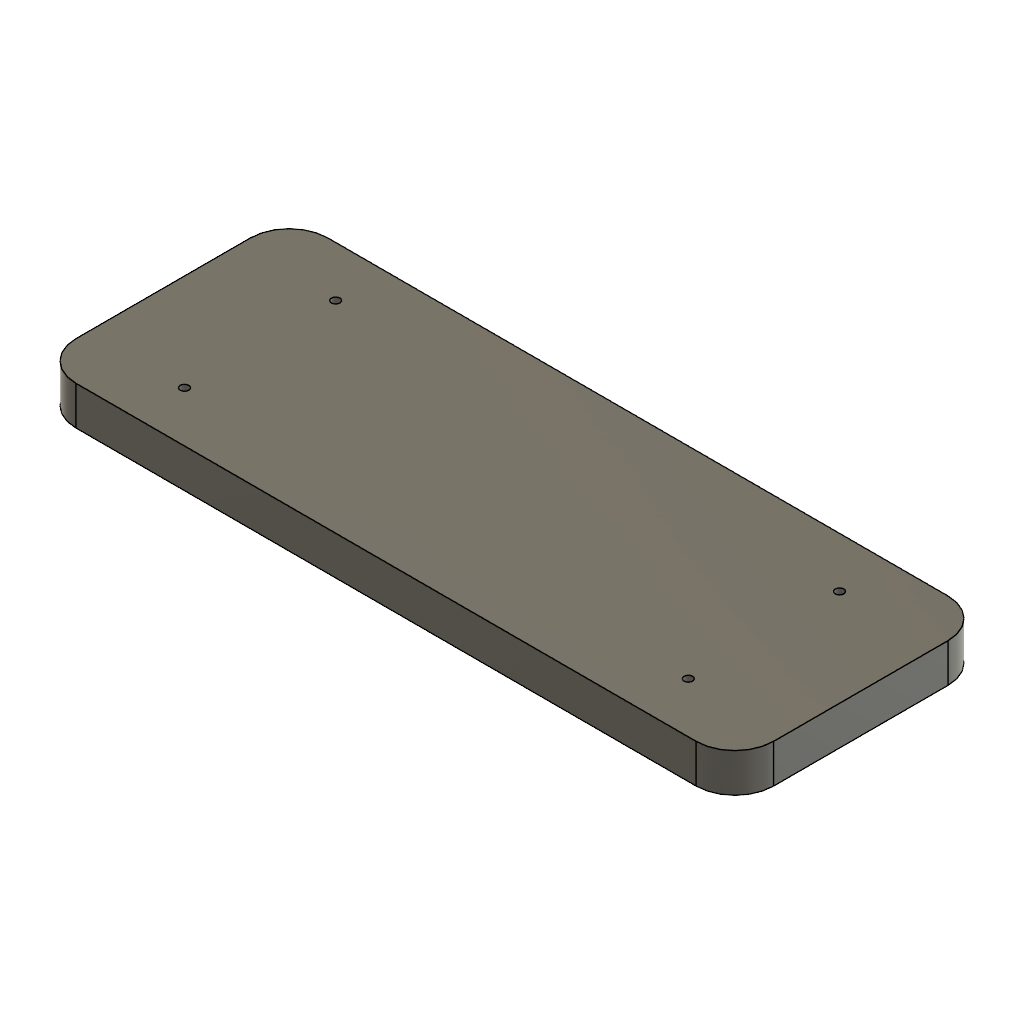
Wood Base (Autodesk Fusion 360 design; units mm, degrees)
Autodesk Fusion 360 part; units mm, degrees
sketch "Sketch1" plane through (0, 0, 0) normal (0, 1, 0) x (1, 0, 0)
  line L0 (12.7, 0) -> (215.8946, 0)
  line L1 (228.5946, 12.7) -> (228.5946, 69.85)
  line L2 (215.8946, 82.55) -> (12.7, 82.55)
  line L3 (0, 69.85) -> (0, 12.7)
  arc A0 (12.7, 82.55) -> (0, 69.85) centre (12.7, 69.85) ccw
  arc A1 (0, 12.7) -> (12.7, 0) centre (12.7, 12.7) ccw
  arc A2 (228.5946, 69.85) -> (215.8946, 82.55) centre (215.8946, 69.85) ccw
  arc A3 (215.8946, 0) -> (228.5946, 12.7) centre (215.8946, 12.7) ccw
  circle A4 centre (31.75, 66.04) radius 1.3894
  line L4 (114.2973, 82.55) -> (114.2973, 0) construction
  line L5 (228.5946, 41.275) -> (0, 41.275) construction
  circle A5 centre (31.75, 66.04) radius 1.3894
  circle A6 centre (31.75, 16.51) radius 1.3894
  circle A7 centre (196.8446, 66.04) radius 1.3894
  circle A8 centre (196.8446, 16.51) radius 1.3894
  point P0 (31.75, 66.04)
  point P1 (31.75, 16.51)
  point P2 (196.8446, 16.51)
  point P3 (196.8446, 66.04)
  dimension "d4" = 12.7
  dimension "d10" = 2.7788
  dimension "d11" = 16.51
  dimension "d12" = 31.75
  constraint horizontal L0
  constraint vertical L1
  constraint horizontal L2
  constraint vertical L3
  constraint tangent L2 A0
  constraint tangent L3 A0
  constraint coincident origin L0
  constraint coincident origin L3
  constraint tangent L0 A1
  constraint tangent L3 A1
  constraint tangent L1 A2
  constraint tangent L2 A2
  constraint equal A1 A2
  constraint tangent L0 A3
  constraint tangent L1 A3
  constraint equal A0 A1
  constraint equal A1 A3
  constraint midpoint L2 L4.start
  constraint midpoint L0 L4.end
  constraint midpoint L1 L5.start
  constraint midpoint L3 L5.end
  constraint equal A4 A6
  constraint symmetric L5 A5 A6
  constraint symmetric L4 A6 A8
  constraint equal A5 A7
  constraint symmetric L5 A7 A8
  constraint coincident P0 A4.centre
  constraint coincident P1 A6.centre
  constraint coincident P2 A8.centre
  constraint coincident P3 A7.centre
  measures "d4" radius of A1
  measures "d10" diameter of A5
  measures "d11" distance of L2 P0
  measures "d12" distance of L3 P0
extrude "Extrude1" add sketch "Sketch1" along normal blind 12.7
